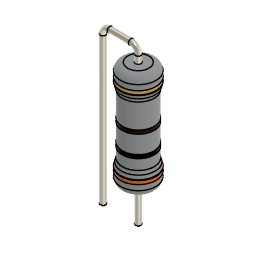
MO-200_(С2-23)_Vert (Autodesk Fusion 360 design; units mm, degrees)
part number: 2026-02-07-17-21-24-598
Autodesk Fusion 360 part; units mm, degrees
ref_plane "WorkPlane1" through (0, 0, 2) normal (0, 0, 1) x (1, 0, 0)
sketch "Sketch2" plane through (0, 0, 2) normal (0, 0, 1) x (1, 0, 0)
  line L0 (0, 0) -> (2.5, 0) construction
  circle A0 centre (2.5, 0) radius 2.5
  point P0 (-2.5, 0)
  point P1 (-2.5, 0)
  point P2 (2.5, 0)
  point P3 (0, -1.75)
  point P4 (0, -22.5)
  dimension "d2" = 2.5
  dimension "d3" = 5
  constraint coincident L0.start origin
  constraint horizontal L0
  constraint coincident L0.end A0.centre
  measures "d2" distance of L0.start L0.end
  measures "d3" diameter of A0
extrude "Extrude1" add sketch "Sketch2" along normal blind 3 makes body 1
sketch "Sketch3" plane through (0, 0, 5) normal (0, 0, 1) x (-1, 0, 0)
  circle A0 centre (-2.5, 0) radius 2.5
  circle A1 centre (-2.5, 0) radius 2.25
  dimension "d6" = 4.5
  constraint concentric A0 A1
  measures "d6" diameter of A1
extrude "Extrude2" add sketch "Sketch3" along normal blind 9 contours A1 bodies 1
sketch "Sketch4" plane through (0, 0, 14) normal (0, 0, 1) x (-1, 0, 0)
  circle A0 centre (-2.5, 0) radius 2.25
  circle A1 centre (-2.5, 0) radius 2.5
  dimension "d9" = 5
  constraint concentric A0 A1
  measures "d9" diameter of A1
extrude "Extrude3" add sketch "Sketch4" along normal blind 3 contours A0 | A1 bodies 1
fillet "Fillet1" radius 1 6 edges at (0.1692, -0.904, 5) (4.5977, -0.8136, 5) (0.1692, -0.904, 2) (4.8308, 0.904, 14) (4.5977, 0.8136, 14) (4.8308, 0.904, 17) on bodies 1
ref_plane "WorkPlane2" through (0, 0, 6.75) normal (0, 0, 1) x (1, 0, 0)
ref_plane "WorkPlane3" through (0, 0, 7.25) normal (0, 0, 1) x (1, 0, 0)
ref_plane "WorkPlane4" through (0, 0, 9.75) normal (0, 0, 1) x (1, 0, 0)
ref_plane "WorkPlane5" through (0, 0, 10.25) normal (0, 0, 1) x (1, 0, 0)
ref_plane "WorkPlane6" through (0, 0, 3.75) normal (0, 0, 1) x (1, 0, 0)
ref_plane "WorkPlane7" through (0, 0, 4.25) normal (0, 0, 1) x (1, 0, 0)
ref_plane "WorkPlane8" through (0, 0, 14.75) normal (0, 0, 1) x (1, 0, 0)
ref_plane "WorkPlane9" through (0, 0, 15.25) normal (0, 0, 1) x (1, 0, 0)
split "Split2" by plane through (0, 0, 3.75) normal (0, 0, 1) and through (0, 0, 4.25) normal (0, 0, 1) and through (0, 0, 6.75) normal (0, 0, 1) and through (0, 0, 7.25) normal (0, 0, 1) and through (0, 0, 9.75) normal (0, 0, 1) and through (0, 0, 10.25) normal (0, 0, 1) and through (0, 0, 14.75) normal (0, 0, 1) and through (0, 0, 15.25) normal (0, 0, 1) bodies 1 makes body 2 at (0.0031, -0.1246, 14.9167) makes body 3 at (0.2528, -0.1122, 8.0833) makes body 4 at (0.2528, -0.1122, 6.9167) makes body 5 at (0.2612, -0.224, 6.2689) makes body 6 at (4.9969, 0.1246, 3.9167) makes body 7 at (0.0304, 0.2471, 16.1893) makes body 8 at (0.2528, -0.1122, 9.9167) makes body 9 at (0.2612, -0.224, 11.3977)
sketch "Sketch5" plane through (0, 0, 2) normal (0, 0, -1) x (1, 0, 0)
  circle A0 centre (2.5, 0) radius 1.5
  circle A1 centre (2.5, 0) radius 0.4
  dimension "d22" = 0.8
  constraint concentric A0 A1
  measures "d22" diameter of A1
extrude "Extrude4" add sketch "Sketch5" along normal blind 5 and the other way blind 16 separate body contours A1 makes body 10
sketch "Sketch6" plane through (0, 0, 0) normal (0, 1, 0) x (1, 0, 0)
  line L0 (-2.5, 3) -> (-2.5, -18)
  arc A0 (-2.5, -18) -> (-1.5, -19) centre (-1.5, -18) ccw
  line L1 (-1.5, -19) -> (1.5, -19)
  arc A1 (1.5, -19) -> (2.5, -18) centre (1.5, -18) ccw
  line L2 (0, -1.75) -> (0, -22.5)
  dimension "d27" = 21
  dimension "d28" = 2.5
  dimension "d29" = 19
  constraint vertical L0
  constraint tangent L0 A0
  constraint tangent A0 L1
  constraint tangent L1 A1
  constraint perpendicular L1 L2
  measures "d27" distance of L0.start L0.end
  measures "d28" distance of origin L0
  measures "d29" distance of origin L1
pipe "Pipe1" add diameter 0.8 path "Sketch6" along A1 L1 A0 L0 bodies 10
split_face "SplitFace1" 1 faces at (2.1005, 0.0199, 11) by plane through (0, 0, 17) normal (0, 0, 1) on bodies 10
fillet "Fillet2" radius 0.2 2 edges at (2.1271, 0.1446, -3) (-2.8729, 0.1446, -3) on bodies 10
equation "d7 = 15 mm - 6 mm"
